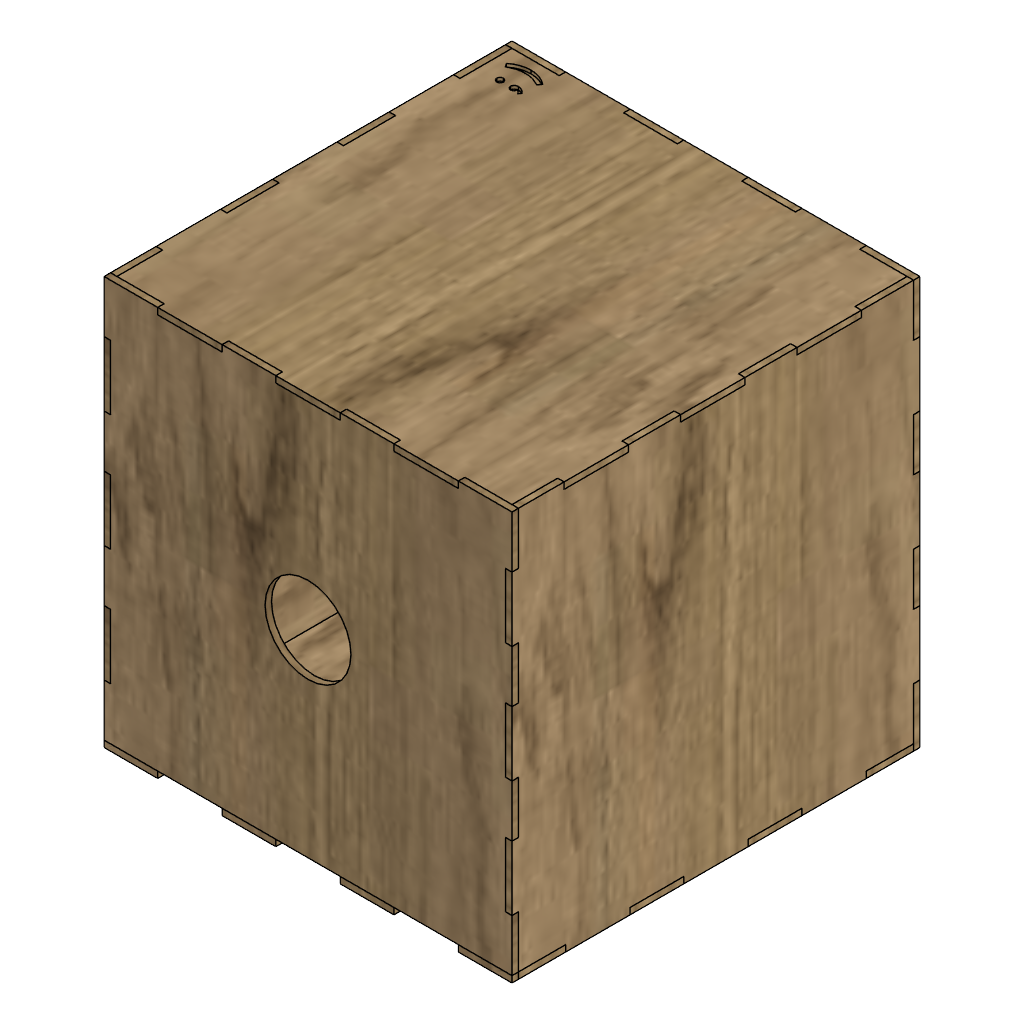
lampara-fisica (Autodesk Fusion 360 design; units mm, degrees)
Autodesk Fusion 360 part; units mm, degrees
sketch "Sketch1" plane through (0, 0, 0) normal (0, 0, 1) x (1, 0, 0)
  line L0 (95, 95) -> (-95, 95)
  line L1 (-95, 95) -> (-95, -95)
  line L2 (-95, -95) -> (95, -95)
  line L3 (95, -95) -> (95, 95)
  line L4 (95, 95) -> (-95, -95) construction
  line L5 (-95, 95) -> (95, -95) construction
  line L6 (-70, 95) -> (-40, 95)
  line L7 (-40, 95) -> (-40, 92)
  line L8 (-40, 92) -> (-70, 92)
  line L9 (-70, 92) -> (-70, 95)
  line L10 (-15, 95) -> (15, 95)
  line L11 (15, 95) -> (15, 92)
  line L12 (15, 92) -> (-15, 92)
  line L13 (-15, 92) -> (-15, 95)
  line L14 (40, 95) -> (70, 95)
  line L15 (70, 95) -> (70, 92)
  line L16 (70, 92) -> (40, 92)
  line L17 (40, 92) -> (40, 95)
  line L18 (-70, 93.5) -> (-95, 93.5) construction
  line L19 (-40, 93.5) -> (-15, 93.5) construction
  line L20 (15, 93.5) -> (40, 93.5) construction
  line L21 (70, 93.5) -> (95, 93.5) construction
  line L22 (20, 0) -> (2.5, 0)
  line L23 (-40, -92) -> (-70, -92)
  line L24 (-70, -92) -> (-70, -95)
  line L25 (-40, -95) -> (-40, -92)
  line L26 (-15, -92) -> (-15, -95)
  line L27 (15, -92) -> (-15, -92)
  line L28 (15, -95) -> (15, -92)
  line L29 (40, -92) -> (40, -95)
  line L30 (70, -92) -> (40, -92)
  line L31 (70, -95) -> (70, -92)
  line L32 (-95, -70) -> (-92, -70)
  line L33 (-92, -70) -> (-92, -40)
  line L34 (-92, -40) -> (-95, -40)
  line L35 (-95, -40) -> (-95, -70)
  line L36 (-95, -15) -> (-92, -15)
  line L37 (-92, -15) -> (-92, 15)
  line L38 (-92, 15) -> (-95, 15)
  line L39 (-95, 15) -> (-95, -15)
  line L40 (-95, 40) -> (-92, 40)
  line L41 (-92, 40) -> (-92, 70)
  line L42 (-92, 70) -> (-95, 70)
  line L43 (-95, 70) -> (-95, 40)
  line L44 (-93.5, -70) -> (-93.5, -95) construction
  line L45 (-93.5, -40) -> (-93.5, -15) construction
  line L46 (-93.5, 15) -> (-93.5, 40) construction
  line L47 (-93.5, 70) -> (-93.5, 95) construction
  line L48 (0, 2.5) -> (0, 20)
  line L49 (92, 70) -> (95, 70)
  line L50 (92, 40) -> (92, 70)
  line L51 (95, 40) -> (92, 40)
  line L52 (92, 15) -> (95, 15)
  line L53 (92, -15) -> (92, 15)
  line L54 (95, -15) -> (92, -15)
  line L55 (92, -40) -> (95, -40)
  line L56 (92, -70) -> (92, -40)
  line L57 (95, -70) -> (92, -70)
  line L58 (0, -90) -> (2, -90)
  line L59 (2, -90) -> (2, -50)
  line L60 (2, -50) -> (0, -50)
  line L61 (0, -50) -> (0, -90)
  line L62 (0, -90) -> (-2, -90) construction
  line L63 (-1, -90) -> (-1, -87) construction
  line L64 (-4, -90) -> (-4, -50)
  line L65 (-2, -50) -> (-2, -90)
  line L66 (-2, -90) -> (-4, -90)
  line L67 (-4, -50) -> (-2, -50)
  point P0 (-70, -93.5)
  dimension "d3" = 190
  dimension "d4" = 190
  dimension "d5" = 3
  dimension "d6" = 30
  dimension "d7" = 30
  dimension "d10" = 2
  dimension "d12" = 2
  dimension "d23" = 3
  constraint horizontal L0
  constraint perpendicular L0 L1
  constraint parallel L0 L2
  constraint parallel L1 L3
  constraint coincident L4 origin
  constraint coincident L5 origin
  constraint horizontal L6
  constraint vertical L7
  constraint horizontal L8
  constraint vertical L9
  constraint coincident L0 L6.start
  constraint horizontal L10
  constraint vertical L11
  constraint horizontal L12
  constraint vertical L13
  constraint coincident L0 L10.start
  constraint horizontal L14
  constraint vertical L15
  constraint horizontal L16
  constraint vertical L17
  constraint coincident L0 L14.start
  constraint midpoint L9 L18.start
  constraint coincident L1 L18.end
  constraint perpendicular L1 L18
  constraint midpoint L7 L19.start
  constraint midpoint L13 L19.end
  constraint perpendicular L13 L19
  constraint midpoint L11 L20.start
  constraint midpoint L17 L20.end
  constraint perpendicular L17 L20
  constraint midpoint L15 L21.start
  constraint coincident L3 L21.end
  constraint perpendicular L3 L21
  constraint equal L18 L19
  constraint equal L19 L20
  constraint equal L20 L21
  constraint equal L8 L12
  constraint equal L12 L16
  constraint symmetric L6.start L22 L24.end
  constraint symmetric L6.end L22 L25.start
  constraint symmetric L7.end L22 L23.start
  constraint symmetric L8.end L22 L23.end
  constraint symmetric L10.start L22 L26.end
  constraint symmetric L10.end L22 L28.start
  constraint symmetric L11.end L22 L27.start
  constraint symmetric L12.end L22 L26.start
  constraint symmetric L14.start L22 L29.end
  constraint symmetric L14.end L22 L31.start
  constraint symmetric L15.end L22 L30.start
  constraint symmetric L16.end L22 L29.start
  constraint symmetric L18.start L22 P0
  constraint horizontal L32
  constraint vertical L33
  constraint horizontal L34
  constraint vertical L35
  constraint coincident L1 L32.start
  constraint horizontal L36
  constraint vertical L37
  constraint horizontal L38
  constraint vertical L39
  constraint coincident L1 L36.start
  constraint horizontal L40
  constraint vertical L41
  constraint horizontal L42
  constraint vertical L43
  constraint coincident L1 L40.start
  constraint midpoint L32 L44.start
  constraint coincident L2 L44.end
  constraint perpendicular L2 L44
  constraint midpoint L34 L45.start
  constraint midpoint L36 L45.end
  constraint perpendicular L36 L45
  constraint midpoint L38 L46.start
  constraint midpoint L40 L46.end
  constraint perpendicular L40 L46
  constraint midpoint L42 L47.start
  constraint coincident L0 L47.end
  constraint perpendicular L0 L47
  constraint equal L46 L47
  constraint equal L45 L46
  constraint equal L44 L45
  constraint equal L37 L41
  constraint equal L33 L37
  constraint symmetric L32.start L48 L57.start
  constraint symmetric L32.end L48 L56.start
  constraint symmetric L33.end L48 L55.start
  constraint symmetric L34.end L48 L55.end
  constraint symmetric L36.start L48 L54.start
  constraint symmetric L36.end L48 L53.start
  constraint symmetric L37.end L48 L52.start
  constraint symmetric L38.end L48 L52.end
  constraint symmetric L40.start L48 L51.start
  constraint symmetric L40.end L48 L50.start
  constraint symmetric L41.end L48 L49.start
  constraint symmetric L42.end L48 L49.end
  constraint horizontal L58
  constraint vertical L59
  constraint horizontal L60
  constraint vertical L61
  constraint perpendicular L61 L62
  constraint midpoint L62 L63.start
  constraint perpendicular L62 L63
  constraint symmetric L58.start L63 L62.end
  constraint symmetric L58.end L63 L64.start
  constraint symmetric L59.end L63 L64.end
  constraint symmetric L60.end L63 L65.start
  measures "d3" distance of L1.end L2.end
  measures "d4" distance of L0.end L1.end
  measures "d5" distance of L6 L8
  measures "d6" distance of L7.end L8.end
  measures "d7" distance of L40.end L41.end
  measures "d10" distance of L58.start L58.end
  measures "d12" distance of L58.start L62.end
  measures "d23" distance of L56.start L57.start
extrude "Extrude2" add sketch "Sketch1" along normal blind 3 contours L0 L1 L2 L3 L7 L8 L9 L11 L12 L13 L15 L16 L17 L23 L24 L25 L26 L27 L28 L29 L30 L31 L32 L33 L34 L36 L37 L38 L40 L41 L42 L49 L50 L51 L52 L53 L54 L55 L56 L57 makes body 1
sketch "Sketch4" plane through (0, 95, 0) normal (0, 1, 0) x (-1, 0, 0)
  line L0 (-95, 0) -> (-70, 0)
  line L1 (-70, 0) -> (-70, 3)
  line L2 (-70, 3) -> (-95, 3)
  line L3 (-95, 3) -> (-95, 0)
  line L4 (40, 0) -> (70, 0)
  line L5 (70, 0) -> (70, 3)
  line L6 (70, 3) -> (40, 3)
  line L7 (40, 3) -> (40, 0)
  line L8 (70, 0) -> (95, 0)
  line L9 (95, 0) -> (95, 3)
  line L10 (95, 3) -> (70, 3)
  line L11 (70, 3) -> (70, 0)
  line L12 (15, 0) -> (40, 0)
  line L13 (40, 0) -> (40, 3)
  line L14 (40, 3) -> (15, 3)
  line L15 (15, 3) -> (15, 0)
  line L16 (-15, 0) -> (15, 0)
  line L17 (15, 0) -> (15, 3)
  line L18 (15, 3) -> (-15, 3)
  line L19 (-15, 3) -> (-15, 0)
  line L20 (-40, 0) -> (-15, 0)
  line L21 (-15, 0) -> (-15, 3)
  line L22 (-15, 3) -> (-40, 3)
  line L23 (-40, 3) -> (-40, 0)
  line L24 (-70, 0) -> (-40, 0)
  line L25 (-40, 0) -> (-40, 3)
  line L26 (-40, 3) -> (-70, 3)
  line L27 (-70, 3) -> (-70, 0)
  line L28 (-95, 0) -> (95, 0)
  line L29 (95, 0) -> (95, 190)
  line L30 (95, 190) -> (-95, 190)
  line L31 (-95, 190) -> (-95, 0)
  line L32 (-95, 165.75) -> (-92, 165.75)
  line L33 (-92, 165.75) -> (-92, 135.75)
  line L34 (-92, 135.75) -> (-95, 135.75)
  line L35 (-95, 135.75) -> (-95, 165.75)
  line L36 (-95, 111.5) -> (-92, 111.5)
  line L37 (-92, 111.5) -> (-92, 81.5)
  line L38 (-92, 81.5) -> (-95, 81.5)
  line L39 (-95, 81.5) -> (-95, 111.5)
  line L40 (-95, 57.25) -> (-92, 57.25)
  line L41 (-92, 57.25) -> (-92, 27.25)
  line L42 (-92, 27.25) -> (-95, 27.25)
  line L43 (-95, 27.25) -> (-95, 57.25)
  line L44 (-70, 190) -> (-40, 190)
  line L45 (-40, 190) -> (-40, 187)
  line L46 (-40, 187) -> (-70, 187)
  line L47 (-70, 187) -> (-70, 190)
  line L48 (-15, 190) -> (15, 190)
  line L49 (15, 190) -> (15, 187)
  line L50 (15, 187) -> (-15, 187)
  line L51 (-15, 187) -> (-15, 190)
  line L52 (40, 190) -> (70, 190)
  line L53 (70, 190) -> (70, 187)
  line L54 (70, 187) -> (40, 187)
  line L55 (40, 187) -> (40, 190)
  line L56 (-93.5, 165.75) -> (-93.5, 190) construction
  line L57 (-93.5, 135.75) -> (-93.5, 111.5) construction
  line L58 (-93.5, 81.5) -> (-93.5, 57.25) construction
  line L59 (-93.5, 27.25) -> (-93.5, 3) construction
  line L60 (-70, 188.5) -> (-95, 188.5) construction
  line L61 (-40, 188.5) -> (-15, 188.5) construction
  line L62 (15, 188.5) -> (40, 188.5) construction
  line L63 (70, 188.5) -> (95, 188.5) construction
  line L64 (0, 20) -> (0, 2.5)
  line L65 (92, 111.5) -> (92, 81.5)
  line L66 (95, 111.5) -> (92, 111.5)
  line L67 (92, 81.5) -> (95, 81.5)
  line L68 (92, 165.75) -> (92, 135.75)
  line L69 (95, 165.75) -> (92, 165.75)
  line L70 (92, 135.75) -> (95, 135.75)
  line L71 (95, 57.25) -> (92, 57.25)
  line L72 (92, 57.25) -> (92, 27.25)
  line L73 (92, 27.25) -> (95, 27.25)
  dimension "d32" = 190
  dimension "d33" = 190
  dimension "d34" = 30
  dimension "d35" = 30
  dimension "d36" = 3
  dimension "d37" = 3
  constraint horizontal L28
  constraint vertical L29
  constraint horizontal L30
  constraint vertical L31
  constraint coincident L0.start L3.end
  constraint horizontal L32
  constraint vertical L33
  constraint horizontal L34
  constraint vertical L35
  constraint coincident L31 L32.start
  constraint horizontal L36
  constraint vertical L37
  constraint horizontal L38
  constraint vertical L39
  constraint coincident L31 L36.start
  constraint horizontal L40
  constraint vertical L41
  constraint horizontal L42
  constraint vertical L43
  constraint coincident L31 L40.start
  constraint horizontal L44
  constraint vertical L45
  constraint horizontal L46
  constraint vertical L47
  constraint coincident L30 L44.start
  constraint horizontal L48
  constraint vertical L49
  constraint horizontal L50
  constraint vertical L51
  constraint coincident L30 L48.start
  constraint horizontal L52
  constraint vertical L53
  constraint horizontal L54
  constraint vertical L55
  constraint coincident L30 L52.start
  constraint midpoint L32 L56.start
  constraint coincident L30 L56.end
  constraint perpendicular L30 L56
  constraint midpoint L34 L57.start
  constraint midpoint L36 L57.end
  constraint perpendicular L36 L57
  constraint midpoint L38 L58.start
  constraint midpoint L40 L58.end
  constraint perpendicular L40 L58
  constraint midpoint L42 L59.start
  constraint coincident L2 L59.end
  constraint perpendicular L2 L59
  constraint equal L56 L57
  constraint equal L57 L58
  constraint equal L58 L59
  constraint equal L33 L37
  constraint equal L33 L41
  constraint midpoint L47 L60.start
  constraint coincident L31 L60.end
  constraint perpendicular L31 L60
  constraint midpoint L45 L61.start
  constraint midpoint L51 L61.end
  constraint perpendicular L51 L61
  constraint midpoint L49 L62.start
  constraint midpoint L55 L62.end
  constraint perpendicular L55 L62
  constraint midpoint L53 L63.start
  constraint coincident L29 L63.end
  constraint perpendicular L29 L63
  constraint equal L60 L61
  constraint equal L60 L62
  constraint equal L62 L63
  constraint equal L50 L54
  constraint equal L46 L50
  constraint symmetric L32.start L64 L69.start
  constraint symmetric L32.end L64 L68.start
  constraint symmetric L33.end L64 L68.end
  constraint symmetric L34.end L64 L70.end
  constraint symmetric L36.start L64 L66.start
  constraint symmetric L36.end L64 L65.start
  constraint symmetric L37.end L64 L65.end
  constraint symmetric L38.end L64 L67.end
  constraint symmetric L40.start L64 L71.start
  constraint symmetric L40.end L64 L71.end
  constraint symmetric L41.end L64 L72.end
  constraint symmetric L42.end L64 L73.end
  measures "d32" distance of L0.start L8.end
  measures "d33" distance of L0.start L30.end
  measures "d34" distance of L32.end L33.end
  measures "d35" distance of L45.end L46.end
  measures "d36" distance of L44.start L46.end
  measures "d37" distance of L33.end L34.end
extrude "Extrude6" cut sketch "Sketch4" against normal blind 3 bodies 1
extrude "Extrude7" add sketch "Sketch4" against normal blind 3 separate body contours L0 L1 L2 L3 L27 L28 L31 | L2 L6 L10 L14 L18 L22 L26 L29 L30 L31 L32 L33 L34 L36 L37 L38 L40 L41 L42 L45 L46 L47 L49 L50 L51 L53 L54 L55 L65 L66 L67 L68 L69 L70 L71 L72 L73 | L19 L20 L21 L22 L23 L25 L28 | L7 L12 L13 L14 L15 L17 L28 | L5 L8 L9 L10 L11 L28 L29 makes body 2
mirror "Mirror1" about plane through (0, 0, 0) normal (0, 1, 0) of bodies 2 makes body 3
sketch "Sketch6" plane through (95, 0, 0) normal (1, 0, 0) x (0, 1, 0)
  line L0 (-95, 190) -> (-95, 165.75)
  line L1 (-95, 165.75) -> (-92, 165.75)
  line L2 (-92, 165.75) -> (-92, 190)
  line L3 (-92, 190) -> (-95, 190)
  line L4 (-95, 165.75) -> (-95, 135.75)
  line L5 (-95, 135.75) -> (-92, 135.75)
  line L6 (-92, 135.75) -> (-92, 165.75)
  line L7 (-92, 165.75) -> (-95, 165.75)
  line L8 (-95, 135.75) -> (-95, 111.5)
  line L9 (-95, 111.5) -> (-92, 111.5)
  line L10 (-92, 111.5) -> (-92, 135.75)
  line L11 (-92, 135.75) -> (-95, 135.75)
  line L12 (-95, 111.5) -> (-95, 81.5)
  line L13 (-95, 81.5) -> (-92, 81.5)
  line L14 (-92, 81.5) -> (-92, 111.5)
  line L15 (-92, 111.5) -> (-95, 111.5)
  line L16 (-95, 81.5) -> (-95, 57.25)
  line L17 (-95, 57.25) -> (-92, 57.25)
  line L18 (-92, 57.25) -> (-92, 81.5)
  line L19 (-92, 81.5) -> (-95, 81.5)
  line L20 (-95, 57.25) -> (-95, 27.25)
  line L21 (-95, 27.25) -> (-92, 27.25)
  line L22 (-92, 27.25) -> (-92, 57.25)
  line L23 (-92, 57.25) -> (-95, 57.25)
  line L24 (-95, 27.25) -> (-95, 0)
  line L25 (-95, 0) -> (-92, 0)
  line L26 (-92, 0) -> (-92, 27.25)
  line L27 (-92, 27.25) -> (-95, 27.25)
  line L28 (-95, 0) -> (-70, 0)
  line L29 (-70, 0) -> (-70, 3)
  line L30 (-70, 3) -> (-95, 3)
  line L31 (-95, 3) -> (-95, 0)
  line L32 (-70, 0) -> (-40, 0)
  line L33 (-40, 0) -> (-40, 3)
  line L34 (-40, 3) -> (-70, 3)
  line L35 (-70, 3) -> (-70, 0)
  line L36 (-40, 0) -> (-15, 0)
  line L37 (-15, 0) -> (-15, 3)
  line L38 (-15, 3) -> (-40, 3)
  line L39 (-40, 3) -> (-40, 0)
  line L40 (-15, 0) -> (15, 0)
  line L41 (15, 0) -> (15, 3)
  line L42 (15, 3) -> (-15, 3)
  line L43 (-15, 3) -> (-15, 0)
  line L44 (15, 0) -> (40, 0)
  line L45 (40, 0) -> (40, 3)
  line L46 (40, 3) -> (15, 3)
  line L47 (15, 3) -> (15, 0)
  line L48 (40, 0) -> (70, 0)
  line L49 (70, 0) -> (70, 3)
  line L50 (70, 3) -> (40, 3)
  line L51 (40, 3) -> (40, 0)
  line L52 (92, 0) -> (92, 3)
  line L53 (92, 3) -> (70, 3)
  line L54 (70, 3) -> (70, 0)
  line L55 (70, 0) -> (92, 0)
  line L56 (95, 0) -> (95, 27.25)
  line L57 (95, 27.25) -> (92, 27.25)
  line L58 (92, 27.25) -> (92, 0)
  line L59 (92, 0) -> (95, 0)
  line L60 (95, 27.25) -> (95, 57.25)
  line L61 (95, 57.25) -> (92, 57.25)
  line L62 (92, 57.25) -> (92, 27.25)
  line L63 (92, 27.25) -> (95, 27.25)
  line L64 (95, 57.25) -> (95, 81.5)
  line L65 (95, 81.5) -> (92, 81.5)
  line L66 (92, 81.5) -> (92, 57.25)
  line L67 (92, 57.25) -> (95, 57.25)
  line L68 (95, 81.5) -> (95, 111.5)
  line L69 (95, 111.5) -> (92, 111.5)
  line L70 (92, 111.5) -> (92, 81.5)
  line L71 (92, 81.5) -> (95, 81.5)
  line L72 (95, 111.5) -> (95, 135.75)
  line L73 (95, 135.75) -> (92, 135.75)
  line L74 (92, 135.75) -> (92, 111.5)
  line L75 (92, 111.5) -> (95, 111.5)
  line L76 (95, 135.75) -> (95, 165.75)
  line L77 (95, 165.75) -> (92, 165.75)
  line L78 (92, 165.75) -> (92, 135.75)
  line L79 (92, 135.75) -> (95, 135.75)
  line L80 (95, 165.75) -> (95, 190)
  line L81 (95, 190) -> (92, 190)
  line L82 (92, 190) -> (92, 165.75)
  line L83 (92, 165.75) -> (95, 165.75)
  line L84 (-95, 190) -> (95, 190)
  line L85 (95, 190) -> (95, 0)
  line L86 (95, 0) -> (-95, 0)
  line L87 (-95, 0) -> (-95, 190)
  line L88 (-70.75, 190) -> (-40.75, 190)
  line L89 (-40.75, 190) -> (-40.75, 187)
  line L90 (-40.75, 187) -> (-70.75, 187)
  line L91 (-70.75, 187) -> (-70.75, 190)
  line L92 (-16.5, 190) -> (13.5, 190)
  line L93 (13.5, 190) -> (13.5, 187)
  line L94 (13.5, 187) -> (-16.5, 187)
  line L95 (-16.5, 187) -> (-16.5, 190)
  line L96 (37.75, 190) -> (67.75, 190)
  line L97 (67.75, 190) -> (67.75, 187)
  line L98 (67.75, 187) -> (37.75, 187)
  line L99 (37.75, 187) -> (37.75, 190)
  line L100 (-95, 186.9289) -> (-70.75, 186.9289) construction
  line L101 (-40.75, 187) -> (-16.5, 187) construction
  line L102 (13.5, 188.5) -> (37.75, 188.5) construction
  line L103 (67.75, 188.5) -> (92, 188.5) construction
  dimension "d48" = 30
  dimension "d49" = 3
  constraint horizontal L84
  constraint vertical L85
  constraint horizontal L86
  constraint vertical L87
  constraint coincident L56.start L59.end
  constraint coincident L0.start L3.end
  constraint horizontal L88
  constraint vertical L89
  constraint horizontal L90
  constraint vertical L91
  constraint coincident L84 L88.start
  constraint horizontal L92
  constraint vertical L93
  constraint horizontal L94
  constraint vertical L95
  constraint coincident L84 L92.start
  constraint horizontal L96
  constraint vertical L97
  constraint horizontal L98
  constraint vertical L99
  constraint coincident L84 L96.start
  constraint coincident L87 L100.start
  constraint coincident L91 L100.end
  constraint perpendicular L91 L100
  constraint coincident L89 L90.start
  constraint coincident L95 L94.end
  constraint perpendicular L95 L101
  constraint midpoint L93 L102.start
  constraint midpoint L99 L102.end
  constraint perpendicular L99 L102
  constraint midpoint L97 L103.start
  constraint coincident L82 L103.end
  constraint perpendicular L82 L103
  constraint equal L100 L101
  constraint equal L101 L102
  constraint equal L102 L103
  constraint equal L90 L94
  constraint equal L94 L98
  constraint equal L91 L95
  measures "d48" distance of L89.end L90.end
  measures "d49" distance of L88.start L90.end
extrude "Extrude10" add sketch "Sketch6" against normal blind 3 separate body contours L1 L4 L5 L6 L7 L11 L87 | L2 L6 L10 L14 L18 L22 L26 L30 L34 L38 L42 L46 L50 L53 L58 L62 L66 L70 L74 L78 L82 L84 L89 L90 L91 L93 L94 L95 L97 L98 L99 | L9 L12 L13 L14 L15 L19 L87 | L17 L20 L21 L22 L23 L27 L87 | L29 L32 L33 L34 L35 L39 L86 | L73 L76 L77 L78 L79 L83 L85 | L37 L40 L41 L42 L43 L47 L86 | L65 L68 L69 L70 L71 L75 L85 | L45 L48 L49 L50 L51 L54 L86 | L57 L60 L61 L62 L63 L67 L85 makes body 4
mirror "Mirror2" about plane through (0, 0, 0) normal (1, 0, 0) of bodies 4 makes body 5
ref_plane "WorkPlane2" through (95, 67.75, 190) normal (0, 0, 1) x (1, 0, 0)
ref_plane "WorkPlane3" through (0, -1.5, 96.5) normal (0, 0, 1) x (1, 0, 0)
sketch "Sketch7" plane through (0, 0, 190) normal (0, 0, 1) x (-1, 0, 0)
  line L0 (-95, -95) -> (-70, -95)
  line L1 (-70, -95) -> (-70, -92)
  line L2 (-70, -92) -> (-95, -92)
  line L3 (-95, -92) -> (-95, -95)
  line L4 (-95, -67.75) -> (-95, -92)
  line L5 (-95, -92) -> (-92, -92)
  line L6 (-92, -92) -> (-92, -67.75)
  line L7 (-92, -67.75) -> (-95, -67.75)
  line L8 (-95, -37.75) -> (-95, -67.75)
  line L9 (-95, -67.75) -> (-92, -67.75)
  line L10 (-92, -67.75) -> (-92, -37.75)
  line L11 (-92, -37.75) -> (-95, -37.75)
  line L12 (-95, -13.5) -> (-95, -37.75)
  line L13 (-95, -37.75) -> (-92, -37.75)
  line L14 (-92, -37.75) -> (-92, -13.5)
  line L15 (-92, -13.5) -> (-95, -13.5)
  line L16 (-95, 16.5) -> (-95, -13.5)
  line L17 (-95, -13.5) -> (-92, -13.5)
  line L18 (-92, -13.5) -> (-92, 16.5)
  line L19 (-92, 16.5) -> (-95, 16.5)
  line L20 (-95, 40.75) -> (-95, 16.5)
  line L21 (-95, 16.5) -> (-92, 16.5)
  line L22 (-92, 16.5) -> (-92, 40.75)
  line L23 (-92, 40.75) -> (-95, 40.75)
  line L24 (-95, 70.75) -> (-95, 40.75)
  line L25 (-95, 40.75) -> (-92, 40.75)
  line L26 (-92, 40.75) -> (-92, 70.75)
  line L27 (-92, 70.75) -> (-95, 70.75)
  line L28 (-95, 92) -> (-95, 70.75)
  line L29 (-95, 70.75) -> (-92, 70.75)
  line L30 (-92, 70.75) -> (-92, 92)
  line L31 (-92, 92) -> (-95, 92)
  line L32 (-70, 95) -> (-95, 95)
  line L33 (-95, 95) -> (-95, 92)
  line L34 (-95, 92) -> (-70, 92)
  line L35 (-70, 92) -> (-70, 95)
  line L36 (-40, 95) -> (-70, 95)
  line L37 (-70, 95) -> (-70, 92)
  line L38 (-70, 92) -> (-40, 92)
  line L39 (-40, 92) -> (-40, 95)
  line L40 (-15, 95) -> (-40, 95)
  line L41 (-40, 95) -> (-40, 92)
  line L42 (-40, 92) -> (-15, 92)
  line L43 (-15, 92) -> (-15, 95)
  line L44 (15, 95) -> (-15, 95)
  line L45 (-15, 95) -> (-15, 92)
  line L46 (-15, 92) -> (15, 92)
  line L47 (15, 92) -> (15, 95)
  line L48 (40, 95) -> (15, 95)
  line L49 (15, 95) -> (15, 92)
  line L50 (15, 92) -> (40, 92)
  line L51 (40, 92) -> (40, 95)
  line L52 (70, 95) -> (40, 95)
  line L53 (40, 95) -> (40, 92)
  line L54 (40, 92) -> (70, 92)
  line L55 (70, 92) -> (70, 95)
  line L56 (95, 95) -> (70, 95)
  line L57 (70, 95) -> (70, 92)
  line L58 (70, 92) -> (95, 92)
  line L59 (95, 92) -> (95, 95)
  line L60 (95, 70.75) -> (95, 92)
  line L61 (95, 92) -> (92, 92)
  line L62 (92, 92) -> (92, 70.75)
  line L63 (92, 70.75) -> (95, 70.75)
  line L64 (95, 40.75) -> (95, 70.75)
  line L65 (95, 70.75) -> (92, 70.75)
  line L66 (92, 70.75) -> (92, 40.75)
  line L67 (92, 40.75) -> (95, 40.75)
  line L68 (95, 16.5) -> (95, 40.75)
  line L69 (95, 40.75) -> (92, 40.75)
  line L70 (92, 40.75) -> (92, 16.5)
  line L71 (92, 16.5) -> (95, 16.5)
  line L72 (95, -13.5) -> (95, 16.5)
  line L73 (95, 16.5) -> (92, 16.5)
  line L74 (92, 16.5) -> (92, -13.5)
  line L75 (92, -13.5) -> (95, -13.5)
  line L76 (95, -37.75) -> (95, -13.5)
  line L77 (95, -13.5) -> (92, -13.5)
  line L78 (92, -13.5) -> (92, -37.75)
  line L79 (92, -37.75) -> (95, -37.75)
  line L80 (95, -67.75) -> (95, -37.75)
  line L81 (95, -37.75) -> (92, -37.75)
  line L82 (92, -37.75) -> (92, -67.75)
  line L83 (92, -67.75) -> (95, -67.75)
  line L84 (95, -92) -> (95, -67.75)
  line L85 (95, -67.75) -> (92, -67.75)
  line L86 (92, -67.75) -> (92, -92)
  line L87 (92, -92) -> (95, -92)
  line L88 (70, -95) -> (95, -95)
  line L89 (95, -95) -> (95, -92)
  line L90 (95, -92) -> (70, -92)
  line L91 (70, -92) -> (70, -95)
  line L92 (40, -95) -> (70, -95)
  line L93 (70, -95) -> (70, -92)
  line L94 (70, -92) -> (40, -92)
  line L95 (40, -92) -> (40, -95)
  line L96 (15, -95) -> (40, -95)
  line L97 (40, -95) -> (40, -92)
  line L98 (40, -92) -> (15, -92)
  line L99 (15, -92) -> (15, -95)
  line L100 (-15, -95) -> (15, -95)
  line L101 (15, -95) -> (15, -92)
  line L102 (15, -92) -> (-15, -92)
  line L103 (-15, -92) -> (-15, -95)
  line L104 (-40, -95) -> (-15, -95)
  line L105 (-15, -95) -> (-15, -92)
  line L106 (-15, -92) -> (-40, -92)
  line L107 (-40, -92) -> (-40, -95)
  line L108 (-70, -95) -> (-40, -95)
  line L109 (-40, -95) -> (-40, -92)
  line L110 (-40, -92) -> (-70, -92)
  line L111 (-70, -92) -> (-70, -95)
  line L112 (95, -95) -> (-95, -95)
  line L113 (-95, -95) -> (-95, 95)
  line L114 (-95, 95) -> (95, 95)
  line L115 (95, 95) -> (95, -95)
  constraint horizontal L112
  constraint vertical L113
  constraint horizontal L114
  constraint vertical L115
  constraint coincident L32.end L33.start
  constraint coincident L88.end L89.start
extrude "Extrude11" add sketch "Sketch7" against normal blind 3 separate body contours L1 L107 L108 L109 L110 L111 L112 | L2 L6 L10 L14 L18 L22 L26 L30 L34 L38 L42 L46 L50 L54 L58 L62 L66 L70 L74 L78 L82 L86 L90 L94 L98 L102 L106 L110 | L7 L8 L9 L10 L11 L13 L113 | L99 L100 L101 L102 L103 L105 L112 | L15 L16 L17 L18 L19 L21 L113 | L91 L92 L93 L94 L95 L97 L112 | L23 L24 L25 L26 L27 L29 L113 | L79 L80 L81 L82 L83 L85 L115 | L35 L36 L37 L38 L39 L41 L114 | L71 L72 L73 L74 L75 L77 L115 | L43 L44 L45 L46 L47 L49 L114 | L63 L64 L65 L66 L67 L69 L115 | L51 L52 L53 L54 L55 L57 L114 makes body 6
sketch "Sketch8" plane through (0, 0, 190) normal (0, 0, 1) x (-1, 0, 0)
  line L0 (40, 95) -> (40, 92)
  line L1 (40, 92) -> (15, 92)
  line L2 (15, 92) -> (15, 95)
  line L3 (15, 95) -> (-15, 95)
  line L4 (-15, 95) -> (-15, 92)
  line L5 (-15, 92) -> (-40, 92)
  line L6 (-40, 92) -> (-40, 95)
  line L7 (-40, 95) -> (-70, 95)
  line L8 (-70, 95) -> (-70, 92)
  line L9 (-70, 92) -> (-92, 92)
  line L10 (-92, 92) -> (-92, 70.75)
  line L11 (-92, 70.75) -> (-95, 70.75)
  line L12 (-95, 70.75) -> (-95, 40.75)
  line L13 (-95, 40.75) -> (-92, 40.75)
  line L14 (-92, 40.75) -> (-92, 16.5)
  line L15 (-92, 16.5) -> (-95, 16.5)
  line L16 (-95, 16.5) -> (-95, -13.5)
  line L17 (-95, -13.5) -> (-92, -13.5)
  line L18 (-92, -13.5) -> (-92, -37.75)
  line L19 (-92, -37.75) -> (-95, -37.75)
  line L20 (-95, -37.75) -> (-95, -67.75)
  line L21 (-95, -67.75) -> (-92, -67.75)
  line L22 (-92, -67.75) -> (-92, -92)
  line L23 (-92, -92) -> (-70, -92)
  line L24 (-70, -92) -> (-70, -95)
  line L25 (-70, -95) -> (-40, -95)
  line L26 (-40, -95) -> (-40, -92)
  line L27 (-40, -92) -> (-15, -92)
  line L28 (-15, -92) -> (-15, -95)
  line L29 (-15, -95) -> (15, -95)
  line L30 (15, -95) -> (15, -92)
  line L31 (15, -92) -> (40, -92)
  line L32 (40, -92) -> (40, -95)
  line L33 (40, -95) -> (70, -95)
  line L34 (70, -95) -> (70, -92)
  line L35 (70, -92) -> (92, -92)
  line L36 (92, -92) -> (92, -67.75)
  line L37 (92, -67.75) -> (95, -67.75)
  line L38 (95, -67.75) -> (95, -37.75)
  line L39 (95, -37.75) -> (92, -37.75)
  line L40 (92, -37.75) -> (92, -13.5)
  line L41 (92, -13.5) -> (95, -13.5)
  line L42 (95, -13.5) -> (95, 16.5)
  line L43 (95, 16.5) -> (92, 16.5)
  line L44 (92, 16.5) -> (92, 40.75)
  line L45 (92, 40.75) -> (95, 40.75)
  line L46 (95, 40.75) -> (95, 70.75)
  line L47 (95, 70.75) -> (92, 70.75)
  line L48 (92, 70.75) -> (92, 92)
  line L49 (92, 92) -> (70, 92)
  line L50 (70, 92) -> (70, 95)
  line L51 (70, 95) -> (40, 95)
  spline S0 degree 3 poles (80.4105, -76.4206) (80.4105, -77.2619) (81.1371, -77.9692) (81.9592, -77.9692) knots 0 0 0 0 1 1 1 1
  spline S1 degree 3 poles (81.9592, -77.9692) (82.8004, -77.9692) (83.5078, -77.2619) (83.5078, -76.4206) knots 0 0 0 0 1 1 1 1
  spline S2 degree 3 poles (83.5078, -76.4206) (83.5078, -75.5794) (82.8004, -74.8719) (81.9592, -74.8719) knots 0 0 0 0 1 1 1 1
  spline S3 degree 3 poles (81.9592, -74.8719) (81.1371, -74.8719) (80.4105, -75.5794) (80.4105, -76.4206) knots 0 0 0 0 1 1 1 1
  spline S4 degree 3 poles (71.5203, -76.1147) (72.3615, -77.2809) (73.6424, -78.084) (75.0764, -78.084) knots 0 0 0 0 1 1 1 1
  spline S5 degree 3 poles (75.0764, -78.084) (76.3191, -78.084) (77.0265, -77.2619) (77.0265, -76.3632) knots 0 0 0 0 1 1 1 1
  spline S6 degree 3 poles (77.0265, -76.3632) (77.0265, -75.5603) (76.3382, -74.8719) (75.497, -74.8719) knots 0 0 0 0 1 1 1 1
  spline S7 degree 3 poles (75.497, -74.8719) (74.694, -74.8719) (74.1204, -75.4455) (74.1204, -76.172) knots 0 0 0 0 1 1 1 1
  spline S8 degree 3 poles (74.1204, -76.172) (74.1204, -76.3059) (74.1587, -76.478) (74.1969, -76.5353) knots 0 0 0 0 1 1 1 1
  spline S9 degree 3 poles (74.1969, -76.5353) (73.5087, -76.3824) (72.7247, -75.675) (72.3806, -75.0631) knots 0 0 0 0 1 1 1 1
  line L52 (72.3806, -75.0631) -> (71.5203, -76.1147)
  spline S10 degree 3 poles (78.7855, -85.0049) (75.9176, -85.0049) (73.8146, -84.374) (71.5203, -83.0548) knots 0 0 0 0 1 1 1 1
  line L53 (71.5203, -83.0548) -> (70.3349, -84.5844)
  spline S11 degree 3 poles (70.3349, -84.5844) (72.4189, -86.458) (75.7073, -87.6434) (78.7855, -87.6434) knots 0 0 0 0 1 1 1 1
  spline S12 degree 3 poles (78.7855, -87.6434) (81.8636, -87.6434) (85.1329, -86.458) (87.236, -84.5844) knots 0 0 0 0 1 1 1 1
  line L54 (87.236, -84.5844) -> (86.0888, -83.0548)
  spline S13 degree 3 poles (86.0888, -83.0548) (83.7563, -84.374) (81.6533, -85.0049) (78.7855, -85.0049) knots 0 0 0 0 1 1 1 1
  point P0 (6.4823, -3.9688)
extrude "Extrude12" cut sketch "Sketch8" against normal blind 1.5 contours S0 S1 S2 S3 | S4 S5 S6 S7 S8 S9 L52 | S10 L53 S11 S12 L54 S13 bodies 6
hole "Hole1" at (0, -95, 94.9769) direction (0, 1, 0) diameter 40 depth 40 tip angle 118 bodies 3
copy_body "Body->Comp1" bodies 1 removing the originals makes body 7 in component "Base"
copy_body "Body->Comp2" bodies 2 removing the originals makes body 8 in component "Tapa trasera"
copy_body "Body->Comp3" bodies 3 removing the originals makes body 9 in component "Tapa frontal con agujero"
copy_body "Body->Comp4" bodies 4 removing the originals makes body 10 in component "Tapa lateral derecha"
copy_body "Body->Comp5" bodies 5 removing the originals makes body 11 in component "Tapa lateral izquierda"
copy_body "Body->Comp6" bodies 6 removing the originals makes body 12 in component "Tapa Superior"
hole "Hole1'" at (0, 95, 94.9769) direction (0, -1, 0) diameter 2 depth 60 tip angle 118 bodies 8 in component "Tapa trasera"
extrude "Extrude3" [rolled back] along distance 3 taper angle 0
extrude "Extrude4" [rolled back] taper angle 0
split "Split1" [rolled back]
extrude "Extrude5" [rolled back] along distance 3 taper angle 0
delete_body "RemoveBody1" bodies 1
delete_body "RemoveBody2" bodies 13
sketch "Sketch3" plane through (95, 0, 0) normal (1, 0, 0) x (0, 1, 0)
  line L0 (-70, 3) -> (-40, 3)
  line L1 (-40, 3) -> (-40, 0)
  line L2 (-40, 0) -> (-70, 0)
  line L3 (-70, 0) -> (-70, 3)
  line L4 (-15, 3) -> (15, 3)
  line L5 (15, 3) -> (15, 0)
  line L6 (15, 0) -> (-15, 0)
  line L7 (-15, 0) -> (-15, 3)
  line L8 (40, 3) -> (70, 3)
  line L9 (70, 3) -> (70, 0)
  line L10 (70, 0) -> (40, 0)
  line L11 (40, 0) -> (40, 3)
  line L12 (-70, 1.5) -> (-95, 1.5) construction
  line L13 (-40, 1.5) -> (-15, 1.5) construction
  line L14 (15, 1.5) -> (40, 1.5) construction
  line L15 (70, 1.5) -> (95, 1.5) construction
  dimension "d30" = 30
  dimension "d31" = 25
  constraint horizontal L0
  constraint vertical L1
  constraint horizontal L2
  constraint vertical L3
  constraint horizontal L4
  constraint vertical L5
  constraint horizontal L6
  constraint vertical L7
  constraint horizontal L8
  constraint vertical L9
  constraint horizontal L10
  constraint vertical L11
  constraint midpoint L3 L12.start
  constraint perpendicular L3 L12
  constraint midpoint L1 L13.start
  constraint midpoint L7 L13.end
  constraint perpendicular L7 L13
  constraint midpoint L5 L14.start
  constraint midpoint L11 L14.end
  constraint perpendicular L11 L14
  constraint midpoint L9 L15.start
  constraint perpendicular L9 L15
  constraint equal L14 L15
  constraint equal L13 L14
  constraint equal L12 L13
  measures "d30" distance of L8.start L8.end
  measures "d31" distance of L15.start L15.end
component "Base" placed x (1, 0, 0) y (0, 1, 0) z (0, 0, 1) at (0, 0, 0)
component "Tapa trasera" placed x (1, 0, 0) y (0, 1, 0) z (0, 0, 1) at (0, 0, 0)
component "Tapa frontal con agujero" placed x (1, 0, 0) y (0, 1, 0) z (0, 0, 1) at (0, 0, 0)
component "Tapa lateral derecha" placed x (1, 0, 0) y (0, 1, 0) z (0, 0, 1) at (0, 0, 0)
component "Tapa lateral izquierda" placed x (1, 0, 0) y (0, 1, 0) z (0, 0, 1) at (0, 0, 0)
component "Tapa Superior" placed x (1, 0, 0) y (0, 1, 0) z (0, 0, 1) at (0, 0, 0)
equation "ladocubo = 190 mm" comment "Lado del cubo"
equation "anchomaterial = 3 mm" comment "Ancho del material"
equation "d3 = ladocubo"
equation "d4 = ladocubo"
equation "d5 = anchomaterial"
equation "d7 = d6"
equation "d12 = separacion_rendijas"
equation "ancho_rendija = 1 mm"
equation "largo_rendija = 40 mm"
equation "separacion_rendijas = 2 mm"
equation "d16 = anchomaterial"
equation "ancho_solapa = 30 mm"
equation "d23 = anchomaterial"
equation "d24 = anchomaterial"
equation "d26 = -anchomaterial"
equation "d28 = anchomaterial"
equation "d30 = ancho_solapa"
equation "d32 = ladocubo"
equation "d33 = ladocubo"
equation "d34 = ancho_solapa"
equation "d35 = ancho_solapa"
equation "d36 = anchomaterial"
equation "d37 = anchomaterial"
equation "d38 = -anchomaterial"
equation "d40 = -anchomaterial"
equation "d48 = ancho_solapa"
equation "d49 = anchomaterial"
equation "d50 = -anchomaterial"
equation "d57 = -anchomaterial"
equation "calar = 1.5 mm" comment "profundidad para representar una imagen"
equation "d60 = -calar"
named bodies: "Base"
